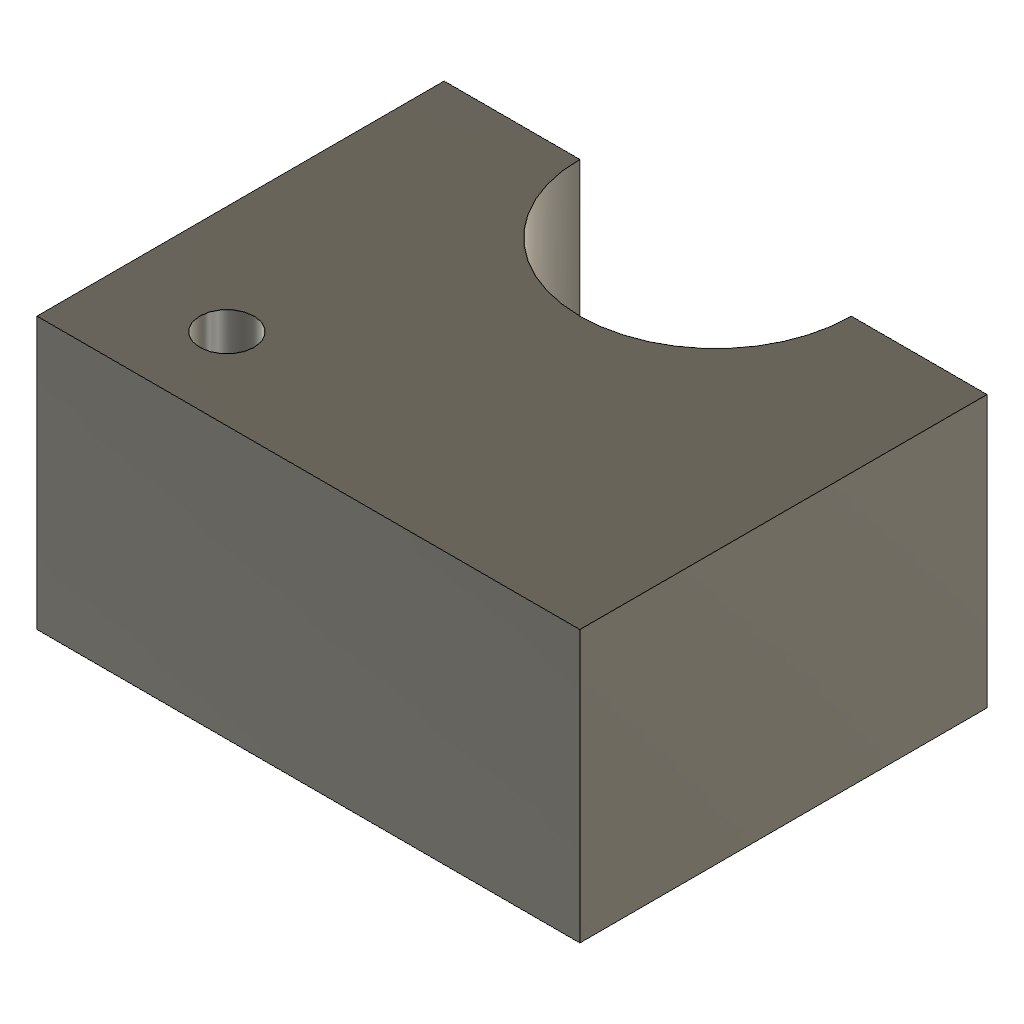
HoleNotch (Autodesk Fusion 360 design; units mm, degrees)
part number: 2026-11-12-16-07-04-066
Autodesk Fusion 360 part; units mm, degrees
sketch "Notch sketch" plane through (0, 0, 0) normal (0, 0, 1) x (1, 0, 0)
  line L0 (0, 0) -> (40, 0)
  line L1 (40, 0) -> (40, 30)
  line L2 (40, 30) -> (30, 30)
  arc A0 (10, 30) -> (30, 30) centre (20, 30) ccw
  line L3 (10, 30) -> (0, 30)
  line L4 (0, 30) -> (0, 0)
extrude "Notch extrude" add sketch "Notch sketch" along normal blind 20
hole "Offset hole" at (8, 6, 20) direction (0, 0, -1) diameter 4 end through all
